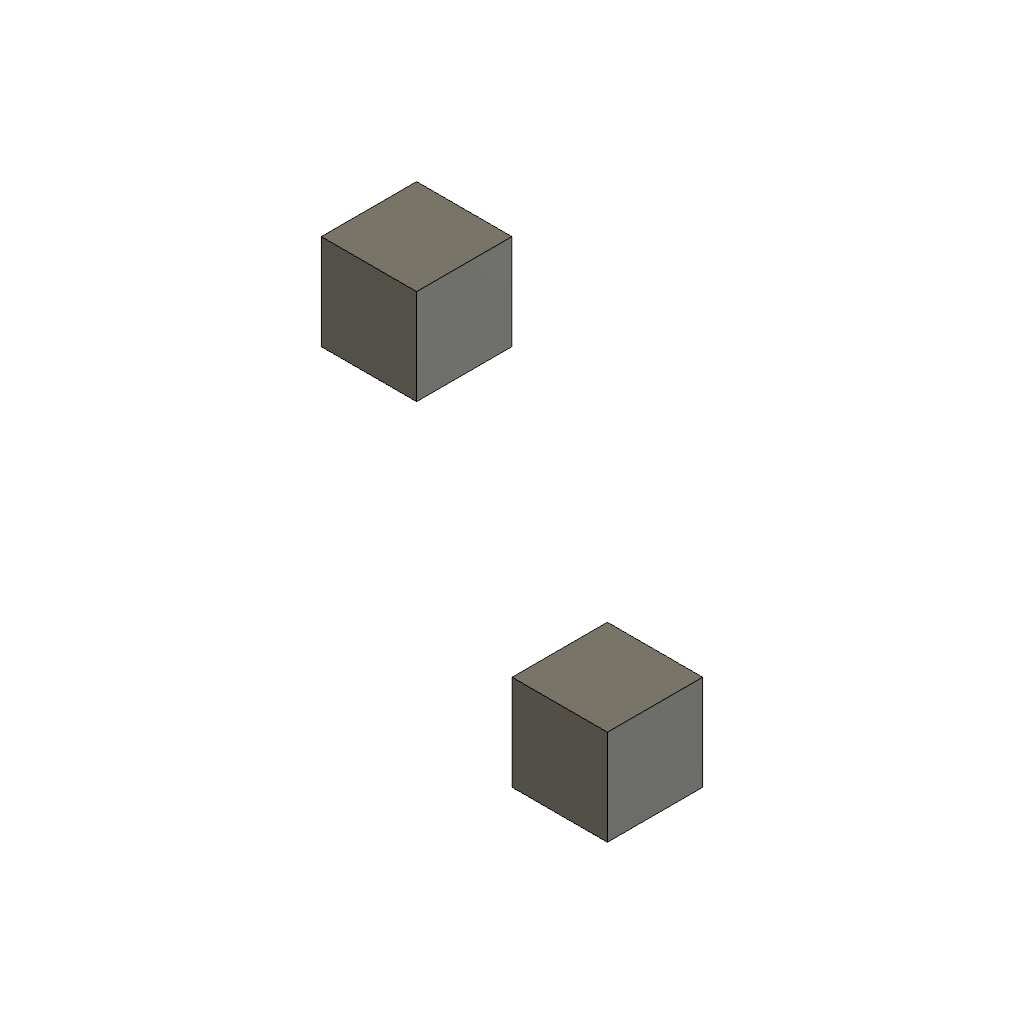
nested_include_children (Autodesk Fusion 360 design; units mm, degrees)
part number: 2026-10-21-12-03-32-822
part number: 2026-10-21-12-03-33-026
part number: 2026-10-21-12-03-33-039
part number: 2026-10-21-12-03-33-042
Autodesk Fusion 360 part; units mm, degrees
sketch "RigidGroupFirstProfile" plane through (0, 0, 0) normal (0, 0, 1) x (1, 0, 0) in component "RigidGroupFirst"
  line L0 (0, 0) -> (10, 0)
  line L1 (10, 0) -> (10, 10)
  line L2 (10, 10) -> (0, 10)
  line L3 (0, 10) -> (0, 0)
extrude "RigidGroupFirstExtrude" add sketch "RigidGroupFirstProfile" along normal blind 10 makes body 1 in component "RigidGroupFirst"
sketch "RigidGroupChildProfile" plane through (0, 0, 0) normal (0, 0, 1) x (1, 0, 0) in component "RigidGroupChild"
  line L0 (0, 0) -> (10, 0)
  line L1 (10, 0) -> (10, 10)
  line L2 (10, 10) -> (0, 10)
  line L3 (0, 10) -> (0, 0)
extrude "RigidGroupChildExtrude" add sketch "RigidGroupChildProfile" along normal blind 10 separate body makes body 2 in component "RigidGroupChild"
component "RigidGroupFirst" placed x (1, 0, 0) y (0, 1, 0) z (0, 0, 1) at (10, 20, 0)
component "RigidGroupParent" placed x (1, 0, 0) y (0, 1, 0) z (0, 0, 1) at (20, 30, 10)
component "RigidGroupChild" placed x (1, 0, 0) y (0, 1, 0) z (0, 0, 1) at (40, -10, 20) in component "RigidGroupParent"
named bodies: "RigidGroupFirstBody", "RigidGroupChildBody"
